Autodesk Fusion 360 part; units mm, degrees
(part 3 of 3)
sketch "Output housing profile" plane through (0, 0, -4.4) normal (0, 0, 1) x (1, 0, 0) in component "Servo motor - tutorial dimensions"
  circle A0 centre (0, -15.093) radius 5.9
extrude "Output housing" add sketch "Output housing profile" along normal blind 4.2 separate body makes body 46 in component "Servo motor - tutorial dimensions"
ref_plane "WorkPlane5" through (0, 0, -10.8) normal (0, 0, 1) x (1, 0, 0) in component "Servo motor - tutorial dimensions"
sketch "Pivot holes (11)" plane through (0, 0, -10.8) normal (0, 0, 1) x (1, 0, 0) in component "Servo motor - tutorial dimensions"
  circle A0 centre (0, -18.893) radius 1.05
  circle A1 centre (0, 8.907) radius 1.05
extrude "Through holes''''''''''" cut sketch "Pivot holes (11)" along normal blind 2.3 bodies 44 in component "Servo motor - tutorial dimensions"
ref_plane "WorkPlane1" through (0, 0, 3) normal (0, 0, 1) x (1, 0, 0) in component "Left mounting bracket"
sketch "Bracket foot profile" plane through (0, 0, 3) normal (0, 0, 1) x (1, 0, 0) in component "Left mounting bracket"
  line L0 (-10, -26) -> (-2, -26)
  line L1 (-2, -26) -> (-2, -17)
  line L2 (-2, -17) -> (-10, -17)
  line L3 (-10, -17) -> (-10, -26)
extrude "Bracket foot" add sketch "Bracket foot profile" along normal blind 3 separate body makes body 47 in component "Left mounting bracket"
ref_plane "WorkPlane2" through (0, 0, 6) normal (0, 0, 1) x (1, 0, 0) in component "Left mounting bracket"
sketch "Upright flange profile" plane through (0, 0, 6) normal (0, 0, 1) x (1, 0, 0) in component "Left mounting bracket"
  line L0 (-10, -26) -> (-2, -26)
  line L1 (-2, -26) -> (-2, -23)
  line L2 (-2, -23) -> (-10, -23)
  line L3 (-10, -23) -> (-10, -26)
extrude "Upright flange" add sketch "Upright flange profile" along normal blind 12 separate body makes body 48 in component "Left mounting bracket"
ref_plane "WorkPlane3" through (0, 0, 3) normal (0, 0, 1) x (1, 0, 0) in component "Left mounting bracket"
sketch "Pivot holes (12)" plane through (0, 0, 3) normal (0, 0, 1) x (1, 0, 0) in component "Left mounting bracket"
  circle A0 centre (-6, -21) radius 1.5
extrude "Through holes (1)''''" cut sketch "Pivot holes (12)" along normal blind 3 bodies 41 in component "Servo pinion - 12T"
extrude "Extrude3" cut sketch "Pivot holes (12)" along normal blind 3 bodies 47 in component "Left mounting bracket"
ref_plane "WorkPlane1" through (0, 0, 3) normal (0, 0, 1) x (1, 0, 0) in component "Right mounting bracket"
sketch "Bracket foot profile (2)" plane through (0, 0, 3) normal (0, 0, 1) x (1, 0, 0) in component "Right mounting bracket"
  line L0 (2, -26) -> (10, -26)
  line L1 (10, -26) -> (10, -17)
  line L2 (10, -17) -> (2, -17)
  line L3 (2, -17) -> (2, -26)
extrude "Bracket foot'" add sketch "Bracket foot profile (2)" along normal blind 3 separate body makes body 49 in component "Right mounting bracket"
ref_plane "WorkPlane2" through (0, 0, 6) normal (0, 0, 1) x (1, 0, 0) in component "Right mounting bracket"
sketch "Upright flange profile (2)" plane through (0, 0, 6) normal (0, 0, 1) x (1, 0, 0) in component "Right mounting bracket"
  line L0 (2, -26) -> (10, -26)
  line L1 (10, -26) -> (10, -23)
  line L2 (10, -23) -> (2, -23)
  line L3 (2, -23) -> (2, -26)
extrude "Upright flange'" add sketch "Upright flange profile (2)" along normal blind 12 separate body makes body 50 in component "Right mounting bracket"
ref_plane "WorkPlane3" through (0, 0, 3) normal (0, 0, 1) x (1, 0, 0) in component "Right mounting bracket"
sketch "Pivot holes (13)" plane through (0, 0, 3) normal (0, 0, 1) x (1, 0, 0) in component "Right mounting bracket"
  circle A0 centre (6, -21) radius 1.5
extrude "Through holes (2)" cut sketch "Pivot holes (13)" along normal blind 3 bodies 41 in component "Servo pinion - 12T"
extrude "Extrude3'" cut sketch "Pivot holes (13)" along normal blind 3 bodies 49 in component "Right mounting bracket"
component "Frame - twin 3 mm plates" placed x (1, 0, 0) y (0, 1, 0) z (0, 0, 1) at (0, 0, 0)
component "Left 24T gear and crank" placed x (1, 0, 0) y (0, 1, 0) z (0, 0, 1) at (0, 0, 0)
component "Left parallel links" placed x (1, 0, 0) y (0, 1, 0) z (0, 0, 1) at (0, 0, 0)
component "Left jaw - twin plates" placed x (1, 0, 0) y (0, 1, 0) z (0, 0, 1) at (0, 0, 0)
component "Left lower crank" placed x (1, 0, 0) y (0, 1, 0) z (0, 0, 1) at (0, 0, 0)
component "Left pivot pin 1" placed x (1, 0, 0) y (0, 1, 0) z (0, 0, 1) at (0, 0, 0)
component "Left pivot pin 2" placed x (1, 0, 0) y (0, 1, 0) z (0, 0, 1) at (0, 0, 0)
component "Left pivot pin 3" placed x (1, 0, 0) y (0, 1, 0) z (0, 0, 1) at (0, 0, 0)
component "Left pivot pin 4" placed x (1, 0, 0) y (0, 1, 0) z (0, 0, 1) at (0, 0, 0)
component "Right 24T gear and crank" placed x (1, 0, 0) y (0, 1, 0) z (0, 0, 1) at (0, 0, 0)
component "Right parallel links" placed x (1, 0, 0) y (0, 1, 0) z (0, 0, 1) at (0, 0, 0)
component "Right jaw - twin plates" placed x (1, 0, 0) y (0, 1, 0) z (0, 0, 1) at (0, 0, 0)
component "Right lower crank" placed x (1, 0, 0) y (0, 1, 0) z (0, 0, 1) at (0, 0, 0)
component "Right pivot pin 1" placed x (1, 0, 0) y (0, 1, 0) z (0, 0, 1) at (0, 0, 0)
component "Right pivot pin 2" placed x (1, 0, 0) y (0, 1, 0) z (0, 0, 1) at (0, 0, 0)
component "Right pivot pin 3" placed x (1, 0, 0) y (0, 1, 0) z (0, 0, 1) at (0, 0, 0)
component "Right pivot pin 4" placed x (1, 0, 0) y (0, 1, 0) z (0, 0, 1) at (0, 0, 0)
component "Servo pinion - 12T" placed x (1, 0, 0) y (0, 1, 0) z (0, 0, 1) at (0, 0, 0)
component "Servo motor - tutorial dimensions" placed x (1, 0, 0) y (0, 1, 0) z (0, 0, 1) at (0, 0, 0)
component "Left mounting bracket" placed x (1, 0, 0) y (0, 1, 0) z (0, 0, 1) at (0, 0, 0)
component "Right mounting bracket" placed x (1, 0, 0) y (0, 1, 0) z (0, 0, 1) at (0, 0, 0)
